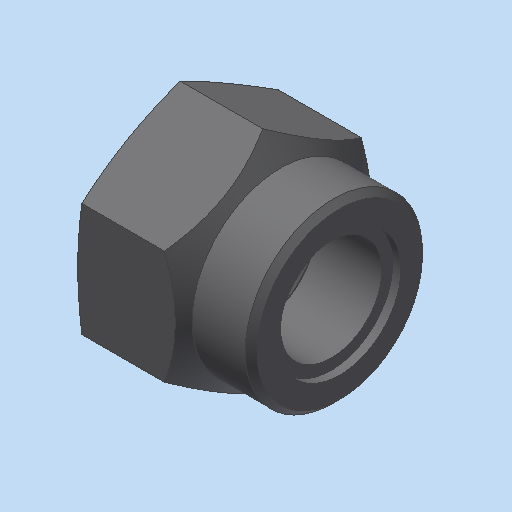
# Autodesk Inventor part: Sechskantmutter_ISO_7040___M5
Saved by Autodesk Inventor 2023.3 (Build 273359000, 359)
## iProperties
Shininess: 64.0
Length Units: 11269
Angle Units: 11279
Time Units: 11290
Mass Units: 11283
Length Display Precision: 3
Angle Display Precision: 2
Compacted: True
Part Number: Sechskantmutter_ISO_7040___M5
Document SubType Name: Modeling
Created: 2004-03-22
Material: xStahl_AnP_Dummymaterial
Description: =<RBPARTNOTITLE2>
Vendor: NORM8
Designer: S.Riedelsheimer
Manufacturer: Standard
Standards Organization: Custom
Density: 7.85 g/cm^3
Mass: 1.83615 g
Surface Area: 3.37403 cm^2
Volume: 0.233905 cm^3
Appearance: Stahl - normal AnP
Density: 0.0
Volumn: 0.0
Area: 0.0
PropertySet Name: Model Information
Control State: 0
Master: False
Checked Out: False
CNS_NB: Sechskantmutter ISO 7040 - M5
CNS_NN: ISO 7040
CNS_NT: Sechskantmutter  mit Klemmteil (mit nichtmetallischem Einsatz) Typ1
CNS_NBSYN: Sechskantmutter ISO 7040 - $NENN.
CNS_LINA: Sechskantmutter ISO 7040 - M5
CNS_NENN: M5
CNS_D: 5.000
CNS_D1: 4.130
CNS_P: 0.800
CNS_DA: 5.750
CNS_DW: 6.880
CNS_E: 8.790
CNS_M: 6.800
CNS_MG: 4.400
CNS_M1: 3.520
CNS_S: 8.000
CNS_KT: DUMMY
PSOL_IDENT_0: {C:\partsolutions8\data\23d-libs\bosch_bamberg\muttern\muttern_mit_klemmteil\din_en_iso_7040.prj},16
PSOL_IDENT_1: 5 {M=Nenngewinde},{VTYP=3D},{NB=Sechskantmutter ISO 7040 - M5},{NN=ISO 7040},{DATE=26.11.2003},{GEOM
PSOL_IDENT_2: DATE=26.11.2003},{VERSION=v2},{LINEID=30},{LINESUBID=-1},{WBVAR=}  {NB=Sechskantmutter ISO 7040 - M5
PSOL_IDENT_3: },{LINA=Sechskantmutter ISO 7040 - M5},{KT=DUMMY},{IDNR=},{NENN=M5},{D=5.000},{D1=4.130},{P=0.800},{
PSOL_IDENT_4: DA=5.750},{DW=6.880},{E=8.790},{M=6.800},{MG=4.400},{M1=3.520},{S=8.000}
RBPARTNOTITLE2: Sechskantmuttern mit Klemmteil (mit nichtmetallischem Einsatz)
RBPARTNOTITLE1: Prevailing torque type hexagon regular nuts (with non-metallic insert)
RBDRAWINGMISSINGSPEC: --
AnP_Kategorie: 4
RBPARTMADEOF: ISO 7040 - M5 - verzinkt
Title: Sechskantmutter ISO 7040 - M5
Author: S.Riedelsheimer
Keywords: =<RBPARTMADEOF>
Comments: =<RBSURFACE2>
Revision Number: 01
Autodesk Inventor part; units mm, degrees
sketch "Sketch_1" plane through (0, 0, 0) normal (0, 0, 1) x (1, 0, 0)
  line L0 (0, 0) -> (6.8, 0)
  line L1 (0, -3.44) -> (0.3737, -4.8345)
  line L2 (0.3737, -4.8345) -> (3.52, -4.8345)
  line L3 (3.52, -4.8345) -> (4.4, -3.6)
  line L4 (4.4, -3.6) -> (6.56, -3.6)
  line L5 (6.56, -3.6) -> (6.8, -3.36)
  line L6 (6.8, -3.36) -> (6.8, -2.5)
  line L7 (6.8, -2.5) -> (6.46, -2.5)
  line L8 (6.46, -2.5) -> (6.46, -2.065)
  line L9 (6.46, -2.065) -> (3.74, -2.065)
  line L10 (3.74, -2.065) -> (3.74, -2.5)
  line L11 (3.74, -2.5) -> (3.4, -2.5)
  line L12 (3.4, -2.5) -> (2.965, -2.065)
  line L13 (2.965, -2.065) -> (0.81, -2.065)
  line L14 (0.81, -2.065) -> (0, -2.875)
  line L15 (0, -2.875) -> (0, -3.44)
  constraints: 32 end point
revolve "Drehung1" add sketch "Sketch_1" angle 360 about axis through (0, 0, 0) along (1, 0, 0)
thread "Gewinde1" size "M5x0.8" class "6H" standard "ANSI Metric M Profile" length 3.025
sketch "Sketch_2" plane through (0, 0, 0) normal (-1, 0, 0) x (0, 0, 1)
  line L0 (8, 8) -> (-8, 8)
  line L1 (-8, 8) -> (-8, -8)
  line L2 (-8, -8) -> (8, -8)
  line L3 (8, -8) -> (8, 8)
  line L4 (2.3094, 4) -> (-2.3094, 4)
  line L5 (-2.3094, 4) -> (-4.6188, 0)
  line L6 (-4.6188, 0) -> (-2.3094, -4)
  line L7 (-2.3094, -4) -> (2.3094, -4)
  line L8 (2.3094, -4) -> (4.6188, 0)
  line L9 (4.6188, 0) -> (2.3094, 4)
  constraints: 20 end point
extrude "Extrusion1" cut sketch "Sketch_2" against normal blind 7.48
ref_plane "IP1_XY" through (0, 0, 0) normal (1, 0, 0) x (0, 0, -1)
ref_plane "IP1_YZ" through (0, 0, 0) normal (0, 0, -1) x (0, 1, 0)
ref_plane "IP2_XY" through (6.8, 0, 0) normal (1, 0, 0) x (0, 0, -1)
ref_plane "IP2_YZ" through (6.8, 0, 0) normal (0, 0, -1) x (0, 1, 0)
